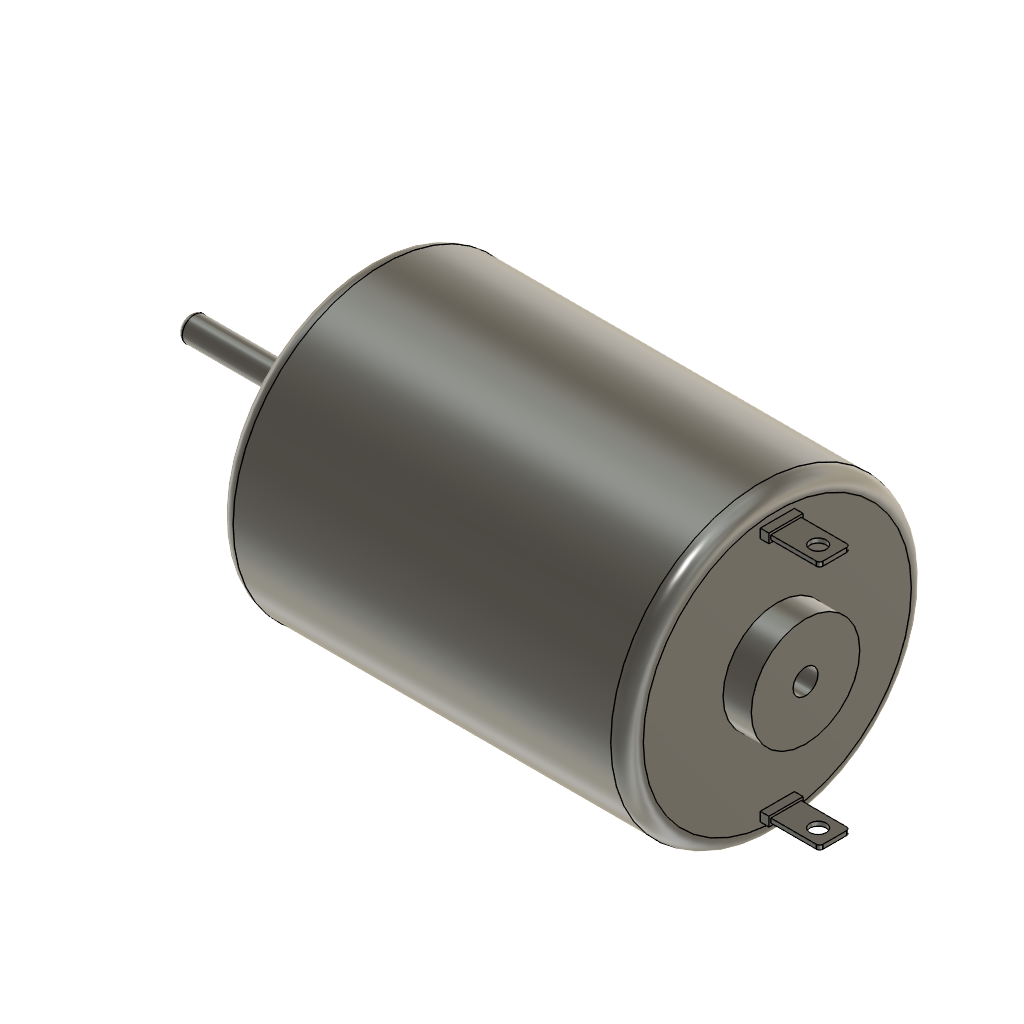
RS385 DC12V Mini Brush DC Motor (Autodesk Fusion 360 design; units mm, degrees)
part number: 2026-10-02-12-18-22-665
Autodesk Fusion 360 part; units mm, degrees
sketch "Sketch1" plane through (0, 0, 0) normal (1, 0, 0) x (0, 1, 0)
  circle A0 centre (0, 0) radius 13.85
  circle A1 centre (0, 0) radius 8
  circle A2 centre (0, 0) radius 5
  circle A3 centre (0, 0) radius 8 construction
  circle A4 centre (0, 8) radius 1.3
  line L0 (20, 0) -> (2.5, 0) construction
  circle A5 centre (0, -8) radius 1.3
  circle A6 centre (0, 0) radius 1.15
  dimension "d1" = 27.7
  dimension "d2" = 16
  dimension "d3" = 10
  dimension "d4" = 16
  dimension "d5" = 2.6
  dimension "d6" = 2.3
  constraint coincident A0.centre A1.centre
  constraint concentric A0 A2
  constraint coincident A1 A4.centre
  constraint symmetric A4 L0 A5
  measures "d1" diameter of A0
  measures "d2" diameter of A1
  measures "d3" diameter of A2
  measures "d4" diameter of A3
  measures "d5" diameter of A4
  measures "d6" diameter of A6
extrude "Extrude1" add sketch "Sketch1" along normal blind 37.8 contours A0 | A1 A4 A5 | A1 A4 | A1 A4 | A1 A5 | A1 A5 | A2 | A6
extrude "Extrude2" add sketch "Sketch1" against normal blind 2.6 contours A2
extrude "Extrude3" add sketch "Sketch1" against normal blind 16.4 contours A6
hole "Hole1" at (0, 0, 8) at (0, 0, -8) direction (1, 0, 0) diameter 2.175 depth 6 tip angle 118
thread "Thread1" "ISO Metric profile 2.6 M2.6x0.45 M2.6x0.45 6H" major diameter 2.675 minor diameter 2.1754 pitch 0.45 angle 60 resizes the face on face at (2, 0.0542, -6.9139) on face at (2, 0.0542, 9.0861)
fillet "Fillet1" radius 1.5 1 edges at (0, -12.9127, -5.0084)
extrude "Extrude4" add sketch "Sketch1" along normal blind 2.6 from surface at 37.8 contours A2
sketch "Sketch2" plane through (37.8, 0, 0) normal (1, 0, 0) x (0, 1, 0)
  circle A0 centre (0, 0) radius 13.85
  circle A1 centre (0, 0) radius 5
  circle A2 centre (0, 0) radius 11.3
  line L0 (1.4, 11.1) -> (-1.4, 11.1)
  line L1 (-1.4, 11.1) -> (-1.4, 11.5)
  line L2 (-1.4, 11.5) -> (1.4, 11.5)
  line L3 (1.4, 11.5) -> (1.4, 11.1)
  line L4 (1.4, 11.1) -> (-1.4, 11.5) construction
  line L5 (-1.4, 11.1) -> (1.4, 11.5) construction
  line L6 (1.5729, 10.8738) -> (-1.5729, 10.8738)
  line L7 (-1.5729, 10.8738) -> (-1.5729, 11.7262)
  line L8 (-1.5729, 11.7262) -> (1.5729, 11.7262)
  line L9 (1.5729, 11.7262) -> (1.5729, 10.8738)
  line L10 (1.5729, 10.8738) -> (-1.5729, 11.7262) construction
  line L11 (-1.5729, 10.8738) -> (1.5729, 11.7262) construction
  point P0 (0, 11.3)
  point P1 (0, 11.3)
  dimension "d23" = 22.6
  dimension "d24" = 2.8
  dimension "d25" = 0.4
  constraint concentric A0 A2
  constraint horizontal L0
  constraint perpendicular L0 L1
  constraint parallel L0 L2
  constraint parallel L1 L3
  constraint coincident L4 P1
  constraint coincident L5 P1
  constraint coincident A2 P1
  constraint horizontal L6
  constraint perpendicular L6 L7
  constraint parallel L6 L8
  constraint parallel L7 L9
  constraint coincident L10 P1
  constraint coincident L11 P1
  constraint coincident P1 P0
  measures "d23" diameter of A2
  measures "d24" distance of L1.end L2.end
  measures "d25" distance of L0.end L1.end
extrude "Extrude5" add sketch "Sketch2" along normal blind 0.8 contours A2 L0 L1 L3 L6 L7 L9 | A2 L1 L2 L3 L7 L8 L9
extrude "Extrude6" add 1 faces at (37.8, -0.4667, 11.3667) along direction (1, 0, 0) blind 5.3
hole "Hole2" at (41.562, 0, 11.5) direction (0, 0, -1) diameter 1.5 depth 2 tip angle 118
mirror "Mirror1" about plane through (0, 0, 0) normal (0, 0, 1) of "Extrude5", "Extrude6"
mirror "Mirror2" about plane through (0, 0, 0) normal (0, 0, 1) of "Hole2"
sketch "Sketch3" plane through (0, 0, 0) normal (-1, 0, 0) x (0, -1, 0)
  circle A0 centre (0, 0) radius 5
  circle A1 centre (0, -8) radius 1.0877
  circle A2 centre (0, 8) radius 1.0877
  circle A3 centre (0, 0) radius 12.35
  arc A4 (-7.584, -5.1579) -> (-5.211, -7.5476) centre (0, 0) ccw
  arc A5 (-5.6462, -3.84) -> (-7.584, -5.1579) centre (-6.6151, -4.499) ccw
  arc A6 (-5.6462, -3.84) -> (-3.8795, -5.6191) centre (0, 0) ccw
  arc A7 (-5.211, -7.5476) -> (-3.8795, -5.6191) centre (-4.5452, -6.5834) ccw
  arc A8 (-6.6151, -4.499) -> (-4.5452, -6.5834) centre (0, 0) ccw construction
  circle A9 centre (0, 0) radius 8
  arc A10 (7.5476, -5.211) -> (5.6191, -3.8795) centre (6.5834, -4.5452) ccw
  arc A11 (5.1579, -7.584) -> (7.5476, -5.211) centre (0, 0) ccw
  arc A12 (3.84, -5.6462) -> (5.1579, -7.584) centre (4.499, -6.6151) ccw
  arc A13 (3.84, -5.6462) -> (5.6191, -3.8795) centre (0, 0) ccw
  arc A14 (5.211, 7.5476) -> (3.8795, 5.6191) centre (4.5452, 6.5834) ccw
  arc A15 (7.584, 5.1579) -> (5.211, 7.5476) centre (0, 0) ccw
  arc A16 (5.6462, 3.84) -> (7.584, 5.1579) centre (6.6151, 4.499) ccw
  arc A17 (5.6462, 3.84) -> (3.8795, 5.6191) centre (0, 0) ccw
  arc A18 (-7.5476, 5.211) -> (-5.6191, 3.8795) centre (-6.5834, 4.5452) ccw
  arc A19 (-5.1579, 7.584) -> (-7.5476, 5.211) centre (0, 0) ccw
  arc A20 (-3.84, 5.6462) -> (-5.1579, 7.584) centre (-4.499, 6.6151) ccw
  arc A21 (-3.84, 5.6462) -> (-5.6191, 3.8795) centre (0, 0) ccw
  dimension "d41" = 360
  constraint tangent A4 A5
  constraint tangent A5 A6
  constraint tangent A6 A7
  constraint tangent A4 A7
  constraint coincident A0.centre A3.centre
  constraint coincident A5.centre A9
extrude "Extrude7" cut sketch "Sketch3" against normal blind 7 contours A9 A10 A12 A13 | A9 A10 A11 A12 | A5 A6 A7 A9 | A4 A5 A7 A9 | A9 A18 A19 A20 | A9 A18 A20 A21 | A9 A14 A16 A17 | A9 A14 A15 A16
fillet "Fillet2" radius 0.5 1 edges at (-16.4, -1.0722, 0.4159)
fillet "Fillet3" radius 1.5 1 edges at (37.8, -12.9127, -5.0084)
fillet "Fillet4" radius 0.3 4 edges at (43.1, -1.4, -11.3) (43.1, 1.4, -11.3) (43.1, -1.4, 11.3) (43.1, 1.4, 11.3)
